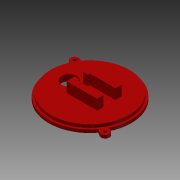
# Autodesk Inventor part: roll_body
Saved by Autodesk Inventor 2014 (Build 180170000, 170)
## iProperties
Created: 2014-09-19
Part Number: roll_body
Material: Všeobecné
Document SubType Name: Modeling
Designer: brodhaq
Density: 1 g/cm^3
Appearance: Výchozí
Author: brodhaq
Autodesk Inventor part; units mm, degrees
ref_plane "YZ Plane" through (0, 0, 0) normal (1, 0, 0) x (0, 1, 0)
ref_plane "XZ Plane" through (0, 0, 0) normal (0, 1, 0) x (-1, 0, 0)
ref_plane "XY Plane" through (0, 0, 0) normal (0, 0, 1) x (1, 0, 0)
sketch "Náčrt1" plane through (0, 0, 0) normal (0, 0, 1) x (1, 0, 0)
  circle A0 centre (-5.8319, -1.0064) radius 38.5
  line L0 (-16.8319, 10.9936) -> (13.1681, 10.9936)
  line L1 (13.1681, 10.9936) -> (13.1681, 4.9936)
  line L2 (13.1681, 4.9936) -> (-16.8319, 4.9936)
  line L3 (-16.8319, 4.9936) -> (-16.8319, 10.9936)
  line L4 (-16.8319, -7.0064) -> (13.1681, -7.0064)
  line L5 (13.1681, -7.0064) -> (13.1681, -13.0064)
  line L6 (13.1681, -13.0064) -> (-16.8319, -13.0064)
  line L7 (-16.8319, -13.0064) -> (-16.8319, -7.0064)
  line L8 (-16.8319, 4.9936) -> (-11.8319, 4.9936)
  line L9 (-11.8319, 4.9936) -> (-11.8319, -7.0064)
  line L10 (-11.8319, -7.0064) -> (-16.8319, -7.0064)
  line L11 (-16.8319, -7.0064) -> (-16.8319, 4.9936)
  circle A1 centre (-26.2007, -1.0064) radius 7.5
  dimension "d60" = 6
  dimension "d61" = 77
  dimension "d62" = 5
  dimension "d63" = 6
  dimension "d64" = 6
  dimension "d65" = 30
  dimension "d66" = 30
  dimension "d67" = 6
  dimension "d68" = 6
  dimension "d79" = 15
  constraints: 24 end point, 6 parallel, 3 horizontal, 3 perpendicular, 2 centre point, 1 point on line
  measures "d60" distance from line of A0.centre L9
  measures "d61" diameter of A0
  measures "d62" distance between parallel lines of L9 L11
  measures "d63" distance between parallel lines of L6 L4
  measures "d64" distance between parallel lines of L2 L0
  measures "d65" distance between parallel lines of L1 L3
  measures "d66" distance between parallel lines of L5 L7
  measures "d67" distance from line of L2 A0.centre
  measures "d68" distance from line of L4 A0.centre
  measures "d79" diameter of A1
extrude "Vysunutí9" add sketch "Náčrt1" against normal blind 3 contours A0 | L0 L1 L2 L3 | L2 L9 L4 L11 | L4 L5 L6 L7 | A1
extrude "Vysunutí10" add sketch "Náčrt1" along normal blind 10 contours L0 L1 L2 L3 | L2 L9 L4 L11 | L4 L5 L6 L7
sketch "Náčrt5" plane through (-16.8319, -13.0064, 0) normal (-1, 0, 0) x (0, 0, 1)
  line L0 (0, 0) -> (0, 24) projected
  line L1 (0, 0) -> (10, 0) projected
  line L2 (10, 24) -> (10, 0) projected
  line L3 (0, 24) -> (10, 24) projected
  line L4 (0, 16) -> (10, 16)
  line L5 (10, 16) -> (10, 8)
  line L6 (10, 8) -> (0, 8)
  line L7 (0, 8) -> (0, 16)
  point P0 (0, 13.0064)
  dimension "d75" = 8
  dimension "d76" = 8
  constraints: 8 end point, 2 parallel, 2 point on line, 1 horizontal, 1 perpendicular
  measures "d75" distance between parallel lines of L3 L4
  measures "d76" distance between parallel lines of L1 L6
extrude "Vysunutí12" cut sketch "Náčrt5" against normal blind 10 contours L0 L4 L2 L6
extrude "Vysunutí13" cut sketch "Náčrt1" against normal blind 10 contours A1
sketch "Náčrt6" plane through (-5.8319, -1.0064, -3) normal (0, 0, -1) x (-1, 0, 0)
  circle A0 centre (20.3688, 0) radius 7.5 projected
  circle A1 centre (0, 0) radius 38.5 projected
  circle A2 centre (0, 0) radius 38.5
  circle A3 centre (38, -23) radius 1.5
  circle A4 centre (-38, 23) radius 1.5
  circle A5 centre (0, 0) radius 38.5
  line L0 (-38, 23) -> (38, -23) construction
  line L1 (-35.9288, 26.422) -> (-32.4071, 24.2905)
  line L2 (-40.0712, 19.578) -> (-36.5496, 17.4465)
  arc A6 (-35.9288, 26.422) -> (-40.0712, 19.578) centre (-38, 23) ccw
  line L3 (35.9288, -26.422) -> (32.4229, -24.2694)
  line L4 (40.1146, -19.6046) -> (36.4997, -17.5505)
  arc A7 (35.8854, -26.3954) -> (39.8347, -19.4456) centre (38, -23) ccw
  arc A8 (-36.5496, 17.4465) -> (32.4229, -24.2694) centre (0, 0) ccw
  arc A9 (36.4997, -17.5505) -> (-32.4071, 24.2905) centre (0, 0) ccw
  arc A10 (36.4997, -17.5505) -> (-32.4071, 24.2905) centre (0, 0) ccw
  arc A11 (-36.5496, 17.4465) -> (32.4229, -24.2694) centre (0, 0) ccw
  point P0 (-5.8319, 1.0064)
  dimension "d82" = 77
  dimension "d83" = 3
  dimension "d84" = 3
  constraints: 14 point on circle, 10 centre point, 10 end point, 4 coincident, 3 tangent, 2 parallel, 2 point on line, 1 concentric
  measures "d82" diameter of A2
  measures "d83" diameter of A3
  measures "d84" diameter of A4
sketch "Náčrt7" plane through (-5.8319, -1.0064, 0) normal (0, 0, 1) x (1, 0, 0)
  circle A0 centre (-20.3688, 0) radius 7.5 projected
  circle A1 centre (0, 0) radius 38.5
  line L0 (-40.0712, 19.578) -> (-36.5496, 17.4465)
  line L1 (-35.9288, 26.422) -> (-32.4071, 24.2905)
  arc A2 (-35.9288, 26.422) -> (-40.0712, 19.578) centre (-38, 23) ccw
  circle A3 centre (-38, 23) radius 1.5
  line L2 (-38, 23) -> (38, -23) construction
  arc A4 (-36.5496, 17.4465) -> (32.4229, -24.2694) centre (0, 0) ccw
  arc A5 (-36.5496, 17.4465) -> (32.4229, -24.2694) centre (0, 0) ccw
  circle A6 centre (0, 0) radius 38.5
  circle A7 centre (0, 0) radius 38.5
  arc A8 (36.4997, -17.5505) -> (-32.4071, 24.2905) centre (0, 0) ccw
  arc A9 (36.4997, -17.5505) -> (-32.4071, 24.2905) centre (0, 0) ccw
  line L3 (35.9288, -26.422) -> (32.4229, -24.2694)
  circle A10 centre (38, -23) radius 1.5
  arc A11 (35.8854, -26.3954) -> (39.8347, -19.4456) centre (38, -23) ccw
  line L4 (40.1146, -19.6046) -> (36.4997, -17.5505)
  point P0 (5.8319, 1.0064)
  point P1 (-5.8319, 1.0064)
  dimension "d87" = 77
  dimension "d88" = 3
  dimension "d89" = 3
  constraints: 14 point on circle, 11 centre point, 10 end point, 4 coincident, 3 tangent, 2 parallel, 2 point on line, 1 concentric
  measures "d87" diameter of A6
  measures "d88" diameter of A10
  measures "d89" diameter of A3
extrude "Vysunutí15" add sketch "Náčrt7" against normal blind 6 contours A1 | A2 L1 A8 L4 A11 L3 A4 L0
extrude "Vysunutí16" cut sketch "Náčrt7" against normal blind 3 contours A2 L1 A8 L4 A11 L3 A4 L0
